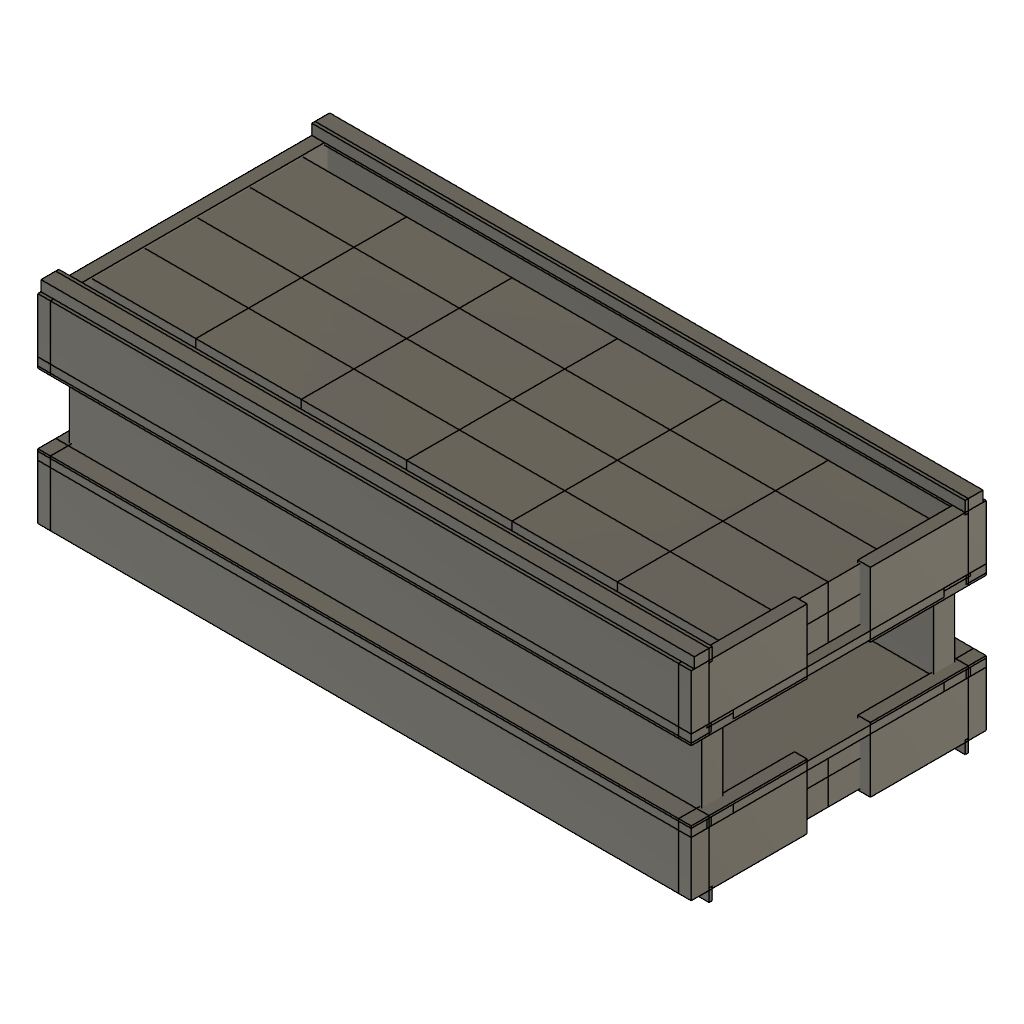
Magnetide-v23-full (Autodesk Fusion 360 design; units mm, degrees)
part number: 2026-10-21-11-29-40-472
Autodesk Fusion 360 part; units mm, degrees
ref_plane "WorkPlane1" through (0, 0, 7.75) normal (0, 0, 1) x (1, 0, 0)
sketch "low_floor_roof" plane through (0, 0, 7.75) normal (0, 0, 1) x (1, 0, 0)
  line L0 (-2, -20) -> (122, -20)
  line L1 (122, -20) -> (122, 20)
  line L2 (122, 20) -> (-2, 20)
  line L3 (-2, 20) -> (-2, -20)
extrude "Extrude1" add sketch "low_floor_roof" along normal mid plane 1.5 makes body 1
ref_plane "WorkPlane2" through (0, 0, 8.25) normal (0, 0, 1) x (1, 0, 0)
sketch "low_seat_R" plane through (0, 0, 8.25) normal (0, 0, 1) x (1, 0, 0)
  line L0 (-2, 20) -> (122, 20)
  line L1 (122, 20) -> (122, 25)
  line L2 (122, 25) -> (-2, 25)
  line L3 (-2, 25) -> (-2, 20)
extrude "Extrude2" add sketch "low_seat_R" along normal mid plane 0.5 separate body makes body 2
ref_plane "WorkPlane3" through (0, 0, 8.25) normal (0, 0, 1) x (1, 0, 0)
sketch "low_seat_L" plane through (0, 0, 8.25) normal (0, 0, 1) x (1, 0, 0)
  line L0 (-2, -25) -> (122, -25)
  line L1 (122, -25) -> (122, -20)
  line L2 (122, -20) -> (-2, -20)
  line L3 (-2, -20) -> (-2, -25)
extrude "Extrude3" add sketch "low_seat_L" along normal mid plane 0.5 separate body makes body 3
ref_plane "WorkPlane4" through (0, 0, 7.75) normal (0, 0, 1) x (1, 0, 0)
sketch "low_out_R" plane through (0, 0, 7.75) normal (0, 0, 1) x (1, 0, 0)
  line L0 (-2, 24.2) -> (122, 24.2)
  line L1 (122, 24.2) -> (122, 28)
  line L2 (122, 28) -> (-2, 28)
  line L3 (-2, 28) -> (-2, 24.2)
extrude "Extrude4" add sketch "low_out_R" along normal mid plane 1.5 separate body makes body 4
ref_plane "WorkPlane5" through (0, 0, 7.75) normal (0, 0, 1) x (1, 0, 0)
sketch "low_out_L" plane through (0, 0, 7.75) normal (0, 0, 1) x (1, 0, 0)
  line L0 (-2, -28) -> (122, -28)
  line L1 (122, -28) -> (122, -24.2)
  line L2 (122, -24.2) -> (-2, -24.2)
  line L3 (-2, -24.2) -> (-2, -28)
extrude "Extrude5" add sketch "low_out_L" along normal mid plane 1.5 separate body makes body 5
ref_plane "WorkPlane6" through (0, 26.3, 0) normal (0, 1, 0) x (0, 0, 1)
sketch "low_wall_R" plane through (0, 26.3, 0) normal (0, 1, 0) x (1, 0, 0)
  line L0 (-2, -18.9) -> (122, -18.9)
  line L1 (122, -18.9) -> (122, -6.6)
  line L2 (122, -6.6) -> (-2, -6.6)
  line L3 (-2, -6.6) -> (-2, -18.9)
extrude "Extrude6" add sketch "low_wall_R" along normal mid plane 3.4 separate body makes body 6
ref_plane "WorkPlane7" through (0, -26.3, 0) normal (0, 1, 0) x (0, 0, 1)
sketch "low_wall_L" plane through (0, -26.3, 0) normal (0, 1, 0) x (1, 0, 0)
  line L0 (-2, -18.9) -> (122, -18.9)
  line L1 (122, -18.9) -> (122, -6.6)
  line L2 (122, -6.6) -> (-2, -6.6)
  line L3 (-2, -6.6) -> (-2, -18.9)
extrude "Extrude7" add sketch "low_wall_L" along normal mid plane 3.4 separate body makes body 7
ref_plane "WorkPlane8" through (-0.8, 0, 0) normal (1, 0, 0) x (0, 1, 0)
sketch "low_end_front" plane through (-0.8, 0, 0) normal (1, 0, 0) x (0, 0, -1)
  line L0 (-18.9, -28) -> (-6.6, -28)
  line L1 (-6.6, -28) -> (-6.6, 28)
  line L2 (-6.6, 28) -> (-18.9, 28)
  line L3 (-18.9, 28) -> (-18.9, -28)
extrude "Extrude8" add sketch "low_end_front" along normal mid plane 2.4 separate body makes body 8
ref_plane "WorkPlane9" through (120.8, 0, 0) normal (1, 0, 0) x (0, 1, 0)
sketch "low_end_back_R" plane through (120.8, 0, 0) normal (1, 0, 0) x (0, 0, -1)
  line L0 (-18.9, 6) -> (-6.6, 6)
  line L1 (-6.6, 6) -> (-6.6, 28)
  line L2 (-6.6, 28) -> (-18.9, 28)
  line L3 (-18.9, 28) -> (-18.9, 6)
extrude "Extrude9" add sketch "low_end_back_R" along normal mid plane 2.4 separate body makes body 9
ref_plane "WorkPlane10" through (120.8, 0, 0) normal (1, 0, 0) x (0, 1, 0)
sketch "low_end_back_L" plane through (120.8, 0, 0) normal (1, 0, 0) x (0, 0, -1)
  line L0 (-18.9, -28) -> (-6.6, -28)
  line L1 (-6.6, -28) -> (-6.6, -6)
  line L2 (-6.6, -6) -> (-18.9, -6)
  line L3 (-18.9, -6) -> (-18.9, -28)
extrude "Extrude10" add sketch "low_end_back_L" along normal mid plane 2.4 separate body makes body 10
ref_plane "WorkPlane11" through (0, 24.3, 0) normal (0, 1, 0) x (0, 0, 1)
sketch "low_lip_R" plane through (0, 24.3, 0) normal (0, 1, 0) x (1, 0, 0)
  line L0 (-2, -20.9) -> (122, -20.9)
  line L1 (122, -20.9) -> (122, -18.5)
  line L2 (122, -18.5) -> (-2, -18.5)
  line L3 (-2, -18.5) -> (-2, -20.9)
extrude "Extrude11" add sketch "low_lip_R" along normal mid plane 0.6 separate body makes body 11
ref_plane "WorkPlane12" through (0, -24.3, 0) normal (0, 1, 0) x (0, 0, 1)
sketch "low_lip_L" plane through (0, -24.3, 0) normal (0, 1, 0) x (1, 0, 0)
  line L0 (-2, -20.9) -> (122, -20.9)
  line L1 (122, -20.9) -> (122, -18.5)
  line L2 (122, -18.5) -> (-2, -18.5)
  line L3 (-2, -18.5) -> (-2, -20.9)
extrude "Extrude12" add sketch "low_lip_L" along normal mid plane 0.6 separate body makes body 12
ref_plane "WorkPlane13" through (0, 0, -7.75) normal (0, 0, 1) x (1, 0, 0)
sketch "up_floor_roof" plane through (0, 0, -7.75) normal (0, 0, 1) x (1, 0, 0)
  line L0 (-2, -20) -> (122, -20)
  line L1 (122, -20) -> (122, 20)
  line L2 (122, 20) -> (-2, 20)
  line L3 (-2, 20) -> (-2, -20)
extrude "Extrude13" add sketch "up_floor_roof" along normal mid plane 1.5 separate body makes body 13
ref_plane "WorkPlane14" through (0, 0, -7.75) normal (0, 0, 1) x (1, 0, 0)
sketch "up_seat_R" plane through (0, 0, -7.75) normal (0, 0, 1) x (1, 0, 0)
  line L0 (-2, 20) -> (122, 20)
  line L1 (122, 20) -> (122, 25)
  line L2 (122, 25) -> (-2, 25)
  line L3 (-2, 25) -> (-2, 20)
extrude "Extrude14" add sketch "up_seat_R" along normal mid plane 1.5 separate body makes body 14
ref_plane "WorkPlane15" through (0, 0, -7.75) normal (0, 0, 1) x (1, 0, 0)
sketch "up_seat_L" plane through (0, 0, -7.75) normal (0, 0, 1) x (1, 0, 0)
  line L0 (-2, -25) -> (122, -25)
  line L1 (122, -25) -> (122, -20)
  line L2 (122, -20) -> (-2, -20)
  line L3 (-2, -20) -> (-2, -25)
extrude "Extrude15" add sketch "up_seat_L" along normal mid plane 1.5 separate body makes body 15
ref_plane "WorkPlane16" through (0, 0, -7.75) normal (0, 0, 1) x (1, 0, 0)
sketch "up_out_R" plane through (0, 0, -7.75) normal (0, 0, 1) x (1, 0, 0)
  line L0 (-2, 24.2) -> (122, 24.2)
  line L1 (122, 24.2) -> (122, 28)
  line L2 (122, 28) -> (-2, 28)
  line L3 (-2, 28) -> (-2, 24.2)
extrude "Extrude16" add sketch "up_out_R" along normal mid plane 1.5 separate body makes body 16
ref_plane "WorkPlane17" through (0, 0, -7.75) normal (0, 0, 1) x (1, 0, 0)
sketch "up_out_L" plane through (0, 0, -7.75) normal (0, 0, 1) x (1, 0, 0)
  line L0 (-2, -28) -> (122, -28)
  line L1 (122, -28) -> (122, -24.2)
  line L2 (122, -24.2) -> (-2, -24.2)
  line L3 (-2, -24.2) -> (-2, -28)
extrude "Extrude17" add sketch "up_out_L" along normal mid plane 1.5 separate body makes body 17
ref_plane "WorkPlane18" through (0, 26.3, 0) normal (0, 1, 0) x (0, 0, 1)
sketch "up_wall_R" plane through (0, 26.3, 0) normal (0, 1, 0) x (1, 0, 0)
  line L0 (-2, 6.6) -> (122, 6.6)
  line L1 (122, 6.6) -> (122, 18.9)
  line L2 (122, 18.9) -> (-2, 18.9)
  line L3 (-2, 18.9) -> (-2, 6.6)
extrude "Extrude18" add sketch "up_wall_R" along normal mid plane 3.4 separate body makes body 18
ref_plane "WorkPlane19" through (0, -26.3, 0) normal (0, 1, 0) x (0, 0, 1)
sketch "up_wall_L" plane through (0, -26.3, 0) normal (0, 1, 0) x (1, 0, 0)
  line L0 (-2, 6.6) -> (122, 6.6)
  line L1 (122, 6.6) -> (122, 18.9)
  line L2 (122, 18.9) -> (-2, 18.9)
  line L3 (-2, 18.9) -> (-2, 6.6)
extrude "Extrude19" add sketch "up_wall_L" along normal mid plane 3.4 separate body makes body 19
ref_plane "WorkPlane20" through (-0.8, 0, 0) normal (1, 0, 0) x (0, 1, 0)
sketch "up_end_front" plane through (-0.8, 0, 0) normal (1, 0, 0) x (0, 0, -1)
  line L0 (6.6, -28) -> (18.9, -28)
  line L1 (18.9, -28) -> (18.9, 28)
  line L2 (18.9, 28) -> (6.6, 28)
  line L3 (6.6, 28) -> (6.6, -28)
extrude "Extrude20" add sketch "up_end_front" along normal mid plane 2.4 separate body makes body 20
ref_plane "WorkPlane21" through (120.8, 0, 0) normal (1, 0, 0) x (0, 1, 0)
sketch "up_end_back_R" plane through (120.8, 0, 0) normal (1, 0, 0) x (0, 0, -1)
  line L0 (6.6, 6) -> (18.9, 6)
  line L1 (18.9, 6) -> (18.9, 28)
  line L2 (18.9, 28) -> (6.6, 28)
  line L3 (6.6, 28) -> (6.6, 6)
extrude "Extrude21" add sketch "up_end_back_R" along normal mid plane 2.4 separate body makes body 21
ref_plane "WorkPlane22" through (120.8, 0, 0) normal (1, 0, 0) x (0, 1, 0)
sketch "up_end_back_L" plane through (120.8, 0, 0) normal (1, 0, 0) x (0, 0, -1)
  line L0 (6.6, -28) -> (18.9, -28)
  line L1 (18.9, -28) -> (18.9, -6)
  line L2 (18.9, -6) -> (6.6, -6)
  line L3 (6.6, -6) -> (6.6, -28)
extrude "Extrude22" add sketch "up_end_back_L" along normal mid plane 2.4 separate body makes body 22
ref_plane "WorkPlane23" through (0, 24.3, 0) normal (0, 1, 0) x (0, 0, 1)
sketch "up_lip_R" plane through (0, 24.3, 0) normal (0, 1, 0) x (1, 0, 0)
  line L0 (-2, 18.5) -> (122, 18.5)
  line L1 (122, 18.5) -> (122, 20.9)
  line L2 (122, 20.9) -> (-2, 20.9)
  line L3 (-2, 20.9) -> (-2, 18.5)
extrude "Extrude23" add sketch "up_lip_R" along normal mid plane 0.6 separate body makes body 23
ref_plane "WorkPlane24" through (0, -24.3, 0) normal (0, 1, 0) x (0, 0, 1)
sketch "up_lip_L" plane through (0, -24.3, 0) normal (0, 1, 0) x (1, 0, 0)
  line L0 (-2, 18.5) -> (122, 18.5)
  line L1 (122, 18.5) -> (122, 20.9)
  line L2 (122, 20.9) -> (-2, 20.9)
  line L3 (-2, 20.9) -> (-2, 18.5)
extrude "Extrude24" add sketch "up_lip_L" along normal mid plane 0.6 separate body makes body 24
ref_plane "WorkPlane25" through (0, 22, 0) normal (0, 1, 0) x (0, 0, 1)
sketch "graphite_R" plane through (0, 22, 0) normal (0, 1, 0) x (1, 0, 0)
  line L0 (0, -8) -> (120, -8)
  line L1 (120, -8) -> (120, 8)
  line L2 (120, 8) -> (0, 8)
  line L3 (0, 8) -> (0, -8)
extrude "Extrude25" add sketch "graphite_R" along normal mid plane 4 separate body makes body 25
ref_plane "WorkPlane26" through (0, -22, 0) normal (0, 1, 0) x (0, 0, 1)
sketch "graphite_L" plane through (0, -22, 0) normal (0, 1, 0) x (1, 0, 0)
  line L0 (0, -8) -> (120, -8)
  line L1 (120, -8) -> (120, 8)
  line L2 (120, 8) -> (0, 8)
  line L3 (0, 8) -> (0, -8)
extrude "Extrude26" add sketch "graphite_L" along normal mid plane 4 separate body makes body 26
ref_plane "WorkPlane27" through (0, 25.7, 0) normal (0, 1, 0) x (0, 0, 1)
sketch "iron_R" plane through (0, 25.7, 0) normal (0, 1, 0) x (1, 0, 0)
  line L0 (-2, -20.9) -> (122, -20.9)
  line L1 (122, -20.9) -> (122, -18.9)
  line L2 (122, -18.9) -> (-2, -18.9)
  line L3 (-2, -18.9) -> (-2, -20.9)
extrude "Extrude27" add sketch "iron_R" along normal mid plane 3.4 separate body makes body 27
ref_plane "WorkPlane28" through (0, -25.7, 0) normal (0, 1, 0) x (0, 0, 1)
sketch "iron_L" plane through (0, -25.7, 0) normal (0, 1, 0) x (1, 0, 0)
  line L0 (-2, -20.9) -> (122, -20.9)
  line L1 (122, -20.9) -> (122, -18.9)
  line L2 (122, -18.9) -> (-2, -18.9)
  line L3 (-2, -18.9) -> (-2, -20.9)
extrude "Extrude28" add sketch "iron_L" along normal mid plane 3.4 separate body makes body 28
ref_plane "WorkPlane29" through (0, 0, 11) normal (0, 0, 1) x (1, 0, 0)
sketch "tile_N_0_0_0" plane through (0, 0, 11) normal (0, 0, 1) x (1, 0, 0)
  line L0 (0, -20) -> (20, -20)
  line L1 (20, -20) -> (20, -10)
  line L2 (20, -10) -> (0, -10)
  line L3 (0, -10) -> (0, -20)
extrude "Extrude29" add sketch "tile_N_0_0_0" along normal mid plane 5 separate body makes body 29
ref_plane "WorkPlane30" through (0, 0, -11) normal (0, 0, 1) x (1, 0, 0)
sketch "tile_S_0_0_0" plane through (0, 0, -11) normal (0, 0, 1) x (1, 0, 0)
  line L0 (0, -20) -> (20, -20)
  line L1 (20, -20) -> (20, -10)
  line L2 (20, -10) -> (0, -10)
  line L3 (0, -10) -> (0, -20)
extrude "Extrude30" add sketch "tile_S_0_0_0" along normal mid plane 5 separate body makes body 30
ref_plane "WorkPlane31" through (0, 0, 16) normal (0, 0, 1) x (1, 0, 0)
sketch "tile_N_0_0_1" plane through (0, 0, 16) normal (0, 0, 1) x (1, 0, 0)
  line L0 (0, -20) -> (20, -20)
  line L1 (20, -20) -> (20, -10)
  line L2 (20, -10) -> (0, -10)
  line L3 (0, -10) -> (0, -20)
extrude "Extrude31" add sketch "tile_N_0_0_1" along normal mid plane 5 separate body makes body 31
ref_plane "WorkPlane32" through (0, 0, -16) normal (0, 0, 1) x (1, 0, 0)
sketch "tile_S_0_0_1" plane through (0, 0, -16) normal (0, 0, 1) x (1, 0, 0)
  line L0 (0, -20) -> (20, -20)
  line L1 (20, -20) -> (20, -10)
  line L2 (20, -10) -> (0, -10)
  line L3 (0, -10) -> (0, -20)
extrude "Extrude32" add sketch "tile_S_0_0_1" along normal mid plane 5 separate body makes body 32
ref_plane "WorkPlane33" through (0, 0, 11) normal (0, 0, 1) x (1, 0, 0)
sketch "tile_N_0_1_0" plane through (0, 0, 11) normal (0, 0, 1) x (1, 0, 0)
  line L0 (0, -10) -> (20, -10)
  line L1 (20, -10) -> (20, 0)
  line L2 (20, 0) -> (0, 0)
  line L3 (0, 0) -> (0, -10)
extrude "Extrude33" add sketch "tile_N_0_1_0" along normal mid plane 5 separate body makes body 33
ref_plane "WorkPlane34" through (0, 0, -11) normal (0, 0, 1) x (1, 0, 0)
sketch "tile_S_0_1_0" plane through (0, 0, -11) normal (0, 0, 1) x (1, 0, 0)
  line L0 (0, -10) -> (20, -10)
  line L1 (20, -10) -> (20, 0)
  line L2 (20, 0) -> (0, 0)
  line L3 (0, 0) -> (0, -10)
extrude "Extrude34" add sketch "tile_S_0_1_0" along normal mid plane 5 separate body makes body 34
ref_plane "WorkPlane35" through (0, 0, 16) normal (0, 0, 1) x (1, 0, 0)
sketch "tile_N_0_1_1" plane through (0, 0, 16) normal (0, 0, 1) x (1, 0, 0)
  line L0 (0, -10) -> (20, -10)
  line L1 (20, -10) -> (20, 0)
  line L2 (20, 0) -> (0, 0)
  line L3 (0, 0) -> (0, -10)
extrude "Extrude35" add sketch "tile_N_0_1_1" along normal mid plane 5 separate body makes body 35
ref_plane "WorkPlane36" through (0, 0, -16) normal (0, 0, 1) x (1, 0, 0)
sketch "tile_S_0_1_1" plane through (0, 0, -16) normal (0, 0, 1) x (1, 0, 0)
  line L0 (0, -10) -> (20, -10)
  line L1 (20, -10) -> (20, 0)
  line L2 (20, 0) -> (0, 0)
  line L3 (0, 0) -> (0, -10)
extrude "Extrude36" add sketch "tile_S_0_1_1" along normal mid plane 5 separate body makes body 36
ref_plane "WorkPlane37" through (0, 0, 11) normal (0, 0, 1) x (1, 0, 0)
sketch "tile_N_0_2_0" plane through (0, 0, 11) normal (0, 0, 1) x (1, 0, 0)
  line L0 (0, 0) -> (20, 0)
  line L1 (20, 0) -> (20, 10)
  line L2 (20, 10) -> (0, 10)
  line L3 (0, 10) -> (0, 0)
extrude "Extrude37" add sketch "tile_N_0_2_0" along normal mid plane 5 separate body makes body 37
ref_plane "WorkPlane38" through (0, 0, -11) normal (0, 0, 1) x (1, 0, 0)
sketch "tile_S_0_2_0" plane through (0, 0, -11) normal (0, 0, 1) x (1, 0, 0)
  line L0 (0, 0) -> (20, 0)
  line L1 (20, 0) -> (20, 10)
  line L2 (20, 10) -> (0, 10)
  line L3 (0, 10) -> (0, 0)
extrude "Extrude38" add sketch "tile_S_0_2_0" along normal mid plane 5 separate body makes body 38
ref_plane "WorkPlane39" through (0, 0, 16) normal (0, 0, 1) x (1, 0, 0)
sketch "tile_N_0_2_1" plane through (0, 0, 16) normal (0, 0, 1) x (1, 0, 0)
  line L0 (0, 0) -> (20, 0)
  line L1 (20, 0) -> (20, 10)
  line L2 (20, 10) -> (0, 10)
  line L3 (0, 10) -> (0, 0)
extrude "Extrude39" add sketch "tile_N_0_2_1" along normal mid plane 5 separate body makes body 39
ref_plane "WorkPlane40" through (0, 0, -16) normal (0, 0, 1) x (1, 0, 0)
sketch "tile_S_0_2_1" plane through (0, 0, -16) normal (0, 0, 1) x (1, 0, 0)
  line L0 (0, 0) -> (20, 0)
  line L1 (20, 0) -> (20, 10)
  line L2 (20, 10) -> (0, 10)
  line L3 (0, 10) -> (0, 0)
extrude "Extrude40" add sketch "tile_S_0_2_1" along normal mid plane 5 separate body makes body 40
ref_plane "WorkPlane41" through (0, 0, 11) normal (0, 0, 1) x (1, 0, 0)
sketch "tile_N_0_3_0" plane through (0, 0, 11) normal (0, 0, 1) x (1, 0, 0)
  line L0 (0, 10) -> (20, 10)
  line L1 (20, 10) -> (20, 20)
  line L2 (20, 20) -> (0, 20)
  line L3 (0, 20) -> (0, 10)
extrude "Extrude41" add sketch "tile_N_0_3_0" along normal mid plane 5 separate body makes body 41
ref_plane "WorkPlane42" through (0, 0, -11) normal (0, 0, 1) x (1, 0, 0)
sketch "tile_S_0_3_0" plane through (0, 0, -11) normal (0, 0, 1) x (1, 0, 0)
  line L0 (0, 10) -> (20, 10)
  line L1 (20, 10) -> (20, 20)
  line L2 (20, 20) -> (0, 20)
  line L3 (0, 20) -> (0, 10)
extrude "Extrude42" add sketch "tile_S_0_3_0" along normal mid plane 5 separate body makes body 42
ref_plane "WorkPlane43" through (0, 0, 16) normal (0, 0, 1) x (1, 0, 0)
sketch "tile_N_0_3_1" plane through (0, 0, 16) normal (0, 0, 1) x (1, 0, 0)
  line L0 (0, 10) -> (20, 10)
  line L1 (20, 10) -> (20, 20)
  line L2 (20, 20) -> (0, 20)
  line L3 (0, 20) -> (0, 10)
extrude "Extrude43" add sketch "tile_N_0_3_1" along normal mid plane 5 separate body makes body 43
ref_plane "WorkPlane44" through (0, 0, -16) normal (0, 0, 1) x (1, 0, 0)
sketch "tile_S_0_3_1" plane through (0, 0, -16) normal (0, 0, 1) x (1, 0, 0)
  line L0 (0, 10) -> (20, 10)
  line L1 (20, 10) -> (20, 20)
  line L2 (20, 20) -> (0, 20)
  line L3 (0, 20) -> (0, 10)
extrude "Extrude44" add sketch "tile_S_0_3_1" along normal mid plane 5 separate body makes body 44
ref_plane "WorkPlane45" through (0, 0, 11) normal (0, 0, 1) x (1, 0, 0)
sketch "tile_N_1_0_0" plane through (0, 0, 11) normal (0, 0, 1) x (1, 0, 0)
  line L0 (20, -20) -> (40, -20)
  line L1 (40, -20) -> (40, -10)
  line L2 (40, -10) -> (20, -10)
  line L3 (20, -10) -> (20, -20)
extrude "Extrude45" add sketch "tile_N_1_0_0" along normal mid plane 5 separate body makes body 45
ref_plane "WorkPlane46" through (0, 0, -11) normal (0, 0, 1) x (1, 0, 0)
sketch "tile_S_1_0_0" plane through (0, 0, -11) normal (0, 0, 1) x (1, 0, 0)
  line L0 (20, -20) -> (40, -20)
  line L1 (40, -20) -> (40, -10)
  line L2 (40, -10) -> (20, -10)
  line L3 (20, -10) -> (20, -20)
extrude "Extrude46" add sketch "tile_S_1_0_0" along normal mid plane 5 separate body makes body 46
ref_plane "WorkPlane47" through (0, 0, 16) normal (0, 0, 1) x (1, 0, 0)
sketch "tile_N_1_0_1" plane through (0, 0, 16) normal (0, 0, 1) x (1, 0, 0)
  line L0 (20, -20) -> (40, -20)
  line L1 (40, -20) -> (40, -10)
  line L2 (40, -10) -> (20, -10)
  line L3 (20, -10) -> (20, -20)
extrude "Extrude47" add sketch "tile_N_1_0_1" along normal mid plane 5 separate body makes body 47
ref_plane "WorkPlane48" through (0, 0, -16) normal (0, 0, 1) x (1, 0, 0)
sketch "tile_S_1_0_1" plane through (0, 0, -16) normal (0, 0, 1) x (1, 0, 0)
  line L0 (20, -20) -> (40, -20)
  line L1 (40, -20) -> (40, -10)
  line L2 (40, -10) -> (20, -10)
  line L3 (20, -10) -> (20, -20)
extrude "Extrude48" add sketch "tile_S_1_0_1" along normal mid plane 5 separate body makes body 48
ref_plane "WorkPlane49" through (0, 0, 11) normal (0, 0, 1) x (1, 0, 0)
sketch "tile_N_1_1_0" plane through (0, 0, 11) normal (0, 0, 1) x (1, 0, 0)
  line L0 (20, -10) -> (40, -10)
  line L1 (40, -10) -> (40, 0)
  line L2 (40, 0) -> (20, 0)
  line L3 (20, 0) -> (20, -10)
extrude "Extrude49" add sketch "tile_N_1_1_0" along normal mid plane 5 separate body makes body 49
ref_plane "WorkPlane50" through (0, 0, -11) normal (0, 0, 1) x (1, 0, 0)
sketch "tile_S_1_1_0" plane through (0, 0, -11) normal (0, 0, 1) x (1, 0, 0)
  line L0 (20, -10) -> (40, -10)
  line L1 (40, -10) -> (40, 0)
  line L2 (40, 0) -> (20, 0)
  line L3 (20, 0) -> (20, -10)
extrude "Extrude50" add sketch "tile_S_1_1_0" along normal mid plane 5 separate body makes body 50
ref_plane "WorkPlane51" through (0, 0, 16) normal (0, 0, 1) x (1, 0, 0)
sketch "tile_N_1_1_1" plane through (0, 0, 16) normal (0, 0, 1) x (1, 0, 0)
  line L0 (20, -10) -> (40, -10)
  line L1 (40, -10) -> (40, 0)
  line L2 (40, 0) -> (20, 0)
  line L3 (20, 0) -> (20, -10)
extrude "Extrude51" add sketch "tile_N_1_1_1" along normal mid plane 5 separate body makes body 51
ref_plane "WorkPlane52" through (0, 0, -16) normal (0, 0, 1) x (1, 0, 0)
sketch "tile_S_1_1_1" plane through (0, 0, -16) normal (0, 0, 1) x (1, 0, 0)
  line L0 (20, -10) -> (40, -10)
  line L1 (40, -10) -> (40, 0)
  line L2 (40, 0) -> (20, 0)
  line L3 (20, 0) -> (20, -10)
extrude "Extrude52" add sketch "tile_S_1_1_1" along normal mid plane 5 separate body makes body 52
ref_plane "WorkPlane53" through (0, 0, 11) normal (0, 0, 1) x (1, 0, 0)
sketch "tile_N_1_2_0" plane through (0, 0, 11) normal (0, 0, 1) x (1, 0, 0)
  line L0 (20, 0) -> (40, 0)
  line L1 (40, 0) -> (40, 10)
  line L2 (40, 10) -> (20, 10)
  line L3 (20, 10) -> (20, 0)
extrude "Extrude53" add sketch "tile_N_1_2_0" along normal mid plane 5 separate body makes body 53
ref_plane "WorkPlane54" through (0, 0, -11) normal (0, 0, 1) x (1, 0, 0)
sketch "tile_S_1_2_0" plane through (0, 0, -11) normal (0, 0, 1) x (1, 0, 0)
  line L0 (20, 0) -> (40, 0)
  line L1 (40, 0) -> (40, 10)
  line L2 (40, 10) -> (20, 10)
  line L3 (20, 10) -> (20, 0)
extrude "Extrude54" add sketch "tile_S_1_2_0" along normal mid plane 5 separate body makes body 54
ref_plane "WorkPlane55" through (0, 0, 16) normal (0, 0, 1) x (1, 0, 0)
sketch "tile_N_1_2_1" plane through (0, 0, 16) normal (0, 0, 1) x (1, 0, 0)
  line L0 (20, 0) -> (40, 0)
  line L1 (40, 0) -> (40, 10)
  line L2 (40, 10) -> (20, 10)
  line L3 (20, 10) -> (20, 0)
extrude "Extrude55" add sketch "tile_N_1_2_1" along normal mid plane 5 separate body makes body 55
ref_plane "WorkPlane56" through (0, 0, -16) normal (0, 0, 1) x (1, 0, 0)
sketch "tile_S_1_2_1" plane through (0, 0, -16) normal (0, 0, 1) x (1, 0, 0)
  line L0 (20, 0) -> (40, 0)
  line L1 (40, 0) -> (40, 10)
  line L2 (40, 10) -> (20, 10)
  line L3 (20, 10) -> (20, 0)
extrude "Extrude56" add sketch "tile_S_1_2_1" along normal mid plane 5 separate body makes body 56
ref_plane "WorkPlane57" through (0, 0, 11) normal (0, 0, 1) x (1, 0, 0)
sketch "tile_N_1_3_0" plane through (0, 0, 11) normal (0, 0, 1) x (1, 0, 0)
  line L0 (20, 10) -> (40, 10)
  line L1 (40, 10) -> (40, 20)
  line L2 (40, 20) -> (20, 20)
  line L3 (20, 20) -> (20, 10)
extrude "Extrude57" add sketch "tile_N_1_3_0" along normal mid plane 5 separate body makes body 57
ref_plane "WorkPlane58" through (0, 0, -11) normal (0, 0, 1) x (1, 0, 0)
sketch "tile_S_1_3_0" plane through (0, 0, -11) normal (0, 0, 1) x (1, 0, 0)
  line L0 (20, 10) -> (40, 10)
  line L1 (40, 10) -> (40, 20)
  line L2 (40, 20) -> (20, 20)
  line L3 (20, 20) -> (20, 10)
extrude "Extrude58" add sketch "tile_S_1_3_0" along normal mid plane 5 separate body makes body 58
ref_plane "WorkPlane59" through (0, 0, 16) normal (0, 0, 1) x (1, 0, 0)
sketch "tile_N_1_3_1" plane through (0, 0, 16) normal (0, 0, 1) x (1, 0, 0)
  line L0 (20, 10) -> (40, 10)
  line L1 (40, 10) -> (40, 20)
  line L2 (40, 20) -> (20, 20)
  line L3 (20, 20) -> (20, 10)
extrude "Extrude59" add sketch "tile_N_1_3_1" along normal mid plane 5 separate body makes body 59
ref_plane "WorkPlane60" through (0, 0, -16) normal (0, 0, 1) x (1, 0, 0)
sketch "tile_S_1_3_1" plane through (0, 0, -16) normal (0, 0, 1) x (1, 0, 0)
  line L0 (20, 10) -> (40, 10)
  line L1 (40, 10) -> (40, 20)
  line L2 (40, 20) -> (20, 20)
  line L3 (20, 20) -> (20, 10)
extrude "Extrude60" add sketch "tile_S_1_3_1" along normal mid plane 5 separate body makes body 60
ref_plane "WorkPlane61" through (0, 0, 11) normal (0, 0, 1) x (1, 0, 0)
sketch "tile_N_2_0_0" plane through (0, 0, 11) normal (0, 0, 1) x (1, 0, 0)
  line L0 (40, -20) -> (60, -20)
  line L1 (60, -20) -> (60, -10)
  line L2 (60, -10) -> (40, -10)
  line L3 (40, -10) -> (40, -20)
extrude "Extrude61" add sketch "tile_N_2_0_0" along normal mid plane 5 separate body makes body 61
ref_plane "WorkPlane62" through (0, 0, -11) normal (0, 0, 1) x (1, 0, 0)
sketch "tile_S_2_0_0" plane through (0, 0, -11) normal (0, 0, 1) x (1, 0, 0)
  line L0 (40, -20) -> (60, -20)
  line L1 (60, -20) -> (60, -10)
  line L2 (60, -10) -> (40, -10)
  line L3 (40, -10) -> (40, -20)
extrude "Extrude62" add sketch "tile_S_2_0_0" along normal mid plane 5 separate body makes body 62
ref_plane "WorkPlane63" through (0, 0, 16) normal (0, 0, 1) x (1, 0, 0)
sketch "tile_N_2_0_1" plane through (0, 0, 16) normal (0, 0, 1) x (1, 0, 0)
  line L0 (40, -20) -> (60, -20)
  line L1 (60, -20) -> (60, -10)
  line L2 (60, -10) -> (40, -10)
  line L3 (40, -10) -> (40, -20)
extrude "Extrude63" add sketch "tile_N_2_0_1" along normal mid plane 5 separate body makes body 63
ref_plane "WorkPlane64" through (0, 0, -16) normal (0, 0, 1) x (1, 0, 0)
sketch "tile_S_2_0_1" plane through (0, 0, -16) normal (0, 0, 1) x (1, 0, 0)
  line L0 (40, -20) -> (60, -20)
  line L1 (60, -20) -> (60, -10)
  line L2 (60, -10) -> (40, -10)
  line L3 (40, -10) -> (40, -20)
extrude "Extrude64" add sketch "tile_S_2_0_1" along normal mid plane 5 separate body makes body 64
ref_plane "WorkPlane65" through (0, 0, 11) normal (0, 0, 1) x (1, 0, 0)
sketch "tile_N_2_1_0" plane through (0, 0, 11) normal (0, 0, 1) x (1, 0, 0)
  line L0 (40, -10) -> (60, -10)
  line L1 (60, -10) -> (60, 0)
  line L2 (60, 0) -> (40, 0)
  line L3 (40, 0) -> (40, -10)
extrude "Extrude65" add sketch "tile_N_2_1_0" along normal mid plane 5 separate body makes body 65
ref_plane "WorkPlane66" through (0, 0, -11) normal (0, 0, 1) x (1, 0, 0)
sketch "tile_S_2_1_0" plane through (0, 0, -11) normal (0, 0, 1) x (1, 0, 0)
  line L0 (40, -10) -> (60, -10)
  line L1 (60, -10) -> (60, 0)
  line L2 (60, 0) -> (40, 0)
  line L3 (40, 0) -> (40, -10)
extrude "Extrude66" add sketch "tile_S_2_1_0" along normal mid plane 5 separate body makes body 66
ref_plane "WorkPlane67" through (0, 0, 16) normal (0, 0, 1) x (1, 0, 0)
sketch "tile_N_2_1_1" plane through (0, 0, 16) normal (0, 0, 1) x (1, 0, 0)
  line L0 (40, -10) -> (60, -10)
  line L1 (60, -10) -> (60, 0)
  line L2 (60, 0) -> (40, 0)
  line L3 (40, 0) -> (40, -10)
extrude "Extrude67" add sketch "tile_N_2_1_1" along normal mid plane 5 separate body makes body 67
ref_plane "WorkPlane68" through (0, 0, -16) normal (0, 0, 1) x (1, 0, 0)
sketch "tile_S_2_1_1" plane through (0, 0, -16) normal (0, 0, 1) x (1, 0, 0)
  line L0 (40, -10) -> (60, -10)
  line L1 (60, -10) -> (60, 0)
  line L2 (60, 0) -> (40, 0)
  line L3 (40, 0) -> (40, -10)
extrude "Extrude68" add sketch "tile_S_2_1_1" along normal mid plane 5 separate body makes body 68
ref_plane "WorkPlane69" through (0, 0, 11) normal (0, 0, 1) x (1, 0, 0)
sketch "tile_N_2_2_0" plane through (0, 0, 11) normal (0, 0, 1) x (1, 0, 0)
  line L0 (40, 0) -> (60, 0)
  line L1 (60, 0) -> (60, 10)
  line L2 (60, 10) -> (40, 10)
  line L3 (40, 10) -> (40, 0)
extrude "Extrude69" add sketch "tile_N_2_2_0" along normal mid plane 5 separate body makes body 69
ref_plane "WorkPlane70" through (0, 0, -11) normal (0, 0, 1) x (1, 0, 0)
sketch "tile_S_2_2_0" plane through (0, 0, -11) normal (0, 0, 1) x (1, 0, 0)
  line L0 (40, 0) -> (60, 0)
  line L1 (60, 0) -> (60, 10)
  line L2 (60, 10) -> (40, 10)
  line L3 (40, 10) -> (40, 0)
extrude "Extrude70" add sketch "tile_S_2_2_0" along normal mid plane 5 separate body makes body 70
ref_plane "WorkPlane71" through (0, 0, 16) normal (0, 0, 1) x (1, 0, 0)
sketch "tile_N_2_2_1" plane through (0, 0, 16) normal (0, 0, 1) x (1, 0, 0)
  line L0 (40, 0) -> (60, 0)
  line L1 (60, 0) -> (60, 10)
  line L2 (60, 10) -> (40, 10)
  line L3 (40, 10) -> (40, 0)
extrude "Extrude71" add sketch "tile_N_2_2_1" along normal mid plane 5 separate body makes body 71
ref_plane "WorkPlane72" through (0, 0, -16) normal (0, 0, 1) x (1, 0, 0)
sketch "tile_S_2_2_1" plane through (0, 0, -16) normal (0, 0, 1) x (1, 0, 0)
  line L0 (40, 0) -> (60, 0)
  line L1 (60, 0) -> (60, 10)
  line L2 (60, 10) -> (40, 10)
  line L3 (40, 10) -> (40, 0)
extrude "Extrude72" add sketch "tile_S_2_2_1" along normal mid plane 5 separate body makes body 72
ref_plane "WorkPlane73" through (0, 0, 11) normal (0, 0, 1) x (1, 0, 0)
sketch "tile_N_2_3_0" plane through (0, 0, 11) normal (0, 0, 1) x (1, 0, 0)
  line L0 (40, 10) -> (60, 10)
  line L1 (60, 10) -> (60, 20)
  line L2 (60, 20) -> (40, 20)
  line L3 (40, 20) -> (40, 10)
extrude "Extrude73" add sketch "tile_N_2_3_0" along normal mid plane 5 separate body makes body 73
ref_plane "WorkPlane74" through (0, 0, -11) normal (0, 0, 1) x (1, 0, 0)
sketch "tile_S_2_3_0" plane through (0, 0, -11) normal (0, 0, 1) x (1, 0, 0)
  line L0 (40, 10) -> (60, 10)
  line L1 (60, 10) -> (60, 20)
  line L2 (60, 20) -> (40, 20)
  line L3 (40, 20) -> (40, 10)
extrude "Extrude74" add sketch "tile_S_2_3_0" along normal mid plane 5 separate body makes body 74
ref_plane "WorkPlane75" through (0, 0, 16) normal (0, 0, 1) x (1, 0, 0)
sketch "tile_N_2_3_1" plane through (0, 0, 16) normal (0, 0, 1) x (1, 0, 0)
  line L0 (40, 10) -> (60, 10)
  line L1 (60, 10) -> (60, 20)
  line L2 (60, 20) -> (40, 20)
  line L3 (40, 20) -> (40, 10)
extrude "Extrude75" add sketch "tile_N_2_3_1" along normal mid plane 5 separate body makes body 75
ref_plane "WorkPlane76" through (0, 0, -16) normal (0, 0, 1) x (1, 0, 0)
sketch "tile_S_2_3_1" plane through (0, 0, -16) normal (0, 0, 1) x (1, 0, 0)
  line L0 (40, 10) -> (60, 10)
  line L1 (60, 10) -> (60, 20)
  line L2 (60, 20) -> (40, 20)
  line L3 (40, 20) -> (40, 10)
extrude "Extrude76" add sketch "tile_S_2_3_1" along normal mid plane 5 separate body makes body 76
ref_plane "WorkPlane77" through (0, 0, 11) normal (0, 0, 1) x (1, 0, 0)
sketch "tile_N_3_0_0" plane through (0, 0, 11) normal (0, 0, 1) x (1, 0, 0)
  line L0 (60, -20) -> (80, -20)
  line L1 (80, -20) -> (80, -10)
  line L2 (80, -10) -> (60, -10)
  line L3 (60, -10) -> (60, -20)
extrude "Extrude77" add sketch "tile_N_3_0_0" along normal mid plane 5 separate body makes body 77
ref_plane "WorkPlane78" through (0, 0, -11) normal (0, 0, 1) x (1, 0, 0)
sketch "tile_S_3_0_0" plane through (0, 0, -11) normal (0, 0, 1) x (1, 0, 0)
  line L0 (60, -20) -> (80, -20)
  line L1 (80, -20) -> (80, -10)
  line L2 (80, -10) -> (60, -10)
  line L3 (60, -10) -> (60, -20)
extrude "Extrude78" add sketch "tile_S_3_0_0" along normal mid plane 5 separate body makes body 78
ref_plane "WorkPlane79" through (0, 0, 16) normal (0, 0, 1) x (1, 0, 0)
sketch "tile_N_3_0_1" plane through (0, 0, 16) normal (0, 0, 1) x (1, 0, 0)
  line L0 (60, -20) -> (80, -20)
  line L1 (80, -20) -> (80, -10)
  line L2 (80, -10) -> (60, -10)
  line L3 (60, -10) -> (60, -20)
extrude "Extrude79" add sketch "tile_N_3_0_1" along normal mid plane 5 separate body makes body 79
ref_plane "WorkPlane80" through (0, 0, -16) normal (0, 0, 1) x (1, 0, 0)
sketch "tile_S_3_0_1" plane through (0, 0, -16) normal (0, 0, 1) x (1, 0, 0)
  line L0 (60, -20) -> (80, -20)
  line L1 (80, -20) -> (80, -10)
  line L2 (80, -10) -> (60, -10)
  line L3 (60, -10) -> (60, -20)
extrude "Extrude80" add sketch "tile_S_3_0_1" along normal mid plane 5 separate body makes body 80
ref_plane "WorkPlane81" through (0, 0, 11) normal (0, 0, 1) x (1, 0, 0)
sketch "tile_N_3_1_0" plane through (0, 0, 11) normal (0, 0, 1) x (1, 0, 0)
  line L0 (60, -10) -> (80, -10)
  line L1 (80, -10) -> (80, 0)
  line L2 (80, 0) -> (60, 0)
  line L3 (60, 0) -> (60, -10)
extrude "Extrude81" add sketch "tile_N_3_1_0" along normal mid plane 5 separate body makes body 81
ref_plane "WorkPlane82" through (0, 0, -11) normal (0, 0, 1) x (1, 0, 0)
sketch "tile_S_3_1_0" plane through (0, 0, -11) normal (0, 0, 1) x (1, 0, 0)
  line L0 (60, -10) -> (80, -10)
  line L1 (80, -10) -> (80, 0)
  line L2 (80, 0) -> (60, 0)
  line L3 (60, 0) -> (60, -10)
extrude "Extrude82" add sketch "tile_S_3_1_0" along normal mid plane 5 separate body makes body 82
ref_plane "WorkPlane83" through (0, 0, 16) normal (0, 0, 1) x (1, 0, 0)
sketch "tile_N_3_1_1" plane through (0, 0, 16) normal (0, 0, 1) x (1, 0, 0)
  line L0 (60, -10) -> (80, -10)
  line L1 (80, -10) -> (80, 0)
  line L2 (80, 0) -> (60, 0)
  line L3 (60, 0) -> (60, -10)
extrude "Extrude83" add sketch "tile_N_3_1_1" along normal mid plane 5 separate body makes body 83
ref_plane "WorkPlane84" through (0, 0, -16) normal (0, 0, 1) x (1, 0, 0)
sketch "tile_S_3_1_1" plane through (0, 0, -16) normal (0, 0, 1) x (1, 0, 0)
  line L0 (60, -10) -> (80, -10)
  line L1 (80, -10) -> (80, 0)
  line L2 (80, 0) -> (60, 0)
  line L3 (60, 0) -> (60, -10)
extrude "Extrude84" add sketch "tile_S_3_1_1" along normal mid plane 5 separate body makes body 84
ref_plane "WorkPlane85" through (0, 0, 11) normal (0, 0, 1) x (1, 0, 0)
sketch "tile_N_3_2_0" plane through (0, 0, 11) normal (0, 0, 1) x (1, 0, 0)
  line L0 (60, 0) -> (80, 0)
  line L1 (80, 0) -> (80, 10)
  line L2 (80, 10) -> (60, 10)
  line L3 (60, 10) -> (60, 0)
extrude "Extrude85" add sketch "tile_N_3_2_0" along normal mid plane 5 separate body makes body 85
ref_plane "WorkPlane86" through (0, 0, -11) normal (0, 0, 1) x (1, 0, 0)
sketch "tile_S_3_2_0" plane through (0, 0, -11) normal (0, 0, 1) x (1, 0, 0)
  line L0 (60, 0) -> (80, 0)
  line L1 (80, 0) -> (80, 10)
  line L2 (80, 10) -> (60, 10)
  line L3 (60, 10) -> (60, 0)
extrude "Extrude86" add sketch "tile_S_3_2_0" along normal mid plane 5 separate body makes body 86
ref_plane "WorkPlane87" through (0, 0, 16) normal (0, 0, 1) x (1, 0, 0)
sketch "tile_N_3_2_1" plane through (0, 0, 16) normal (0, 0, 1) x (1, 0, 0)
  line L0 (60, 0) -> (80, 0)
  line L1 (80, 0) -> (80, 10)
  line L2 (80, 10) -> (60, 10)
  line L3 (60, 10) -> (60, 0)
extrude "Extrude87" add sketch "tile_N_3_2_1" along normal mid plane 5 separate body makes body 87
ref_plane "WorkPlane88" through (0, 0, -16) normal (0, 0, 1) x (1, 0, 0)
sketch "tile_S_3_2_1" plane through (0, 0, -16) normal (0, 0, 1) x (1, 0, 0)
  line L0 (60, 0) -> (80, 0)
  line L1 (80, 0) -> (80, 10)
  line L2 (80, 10) -> (60, 10)
  line L3 (60, 10) -> (60, 0)
extrude "Extrude88" add sketch "tile_S_3_2_1" along normal mid plane 5 separate body makes body 88
ref_plane "WorkPlane89" through (0, 0, 11) normal (0, 0, 1) x (1, 0, 0)
sketch "tile_N_3_3_0" plane through (0, 0, 11) normal (0, 0, 1) x (1, 0, 0)
  line L0 (60, 10) -> (80, 10)
  line L1 (80, 10) -> (80, 20)
  line L2 (80, 20) -> (60, 20)
  line L3 (60, 20) -> (60, 10)
extrude "Extrude89" add sketch "tile_N_3_3_0" along normal mid plane 5 separate body makes body 89
ref_plane "WorkPlane90" through (0, 0, -11) normal (0, 0, 1) x (1, 0, 0)
sketch "tile_S_3_3_0" plane through (0, 0, -11) normal (0, 0, 1) x (1, 0, 0)
  line L0 (60, 10) -> (80, 10)
  line L1 (80, 10) -> (80, 20)
  line L2 (80, 20) -> (60, 20)
  line L3 (60, 20) -> (60, 10)
extrude "Extrude90" add sketch "tile_S_3_3_0" along normal mid plane 5 separate body makes body 90
ref_plane "WorkPlane91" through (0, 0, 16) normal (0, 0, 1) x (1, 0, 0)
sketch "tile_N_3_3_1" plane through (0, 0, 16) normal (0, 0, 1) x (1, 0, 0)
  line L0 (60, 10) -> (80, 10)
  line L1 (80, 10) -> (80, 20)
  line L2 (80, 20) -> (60, 20)
  line L3 (60, 20) -> (60, 10)
extrude "Extrude91" add sketch "tile_N_3_3_1" along normal mid plane 5 separate body makes body 91
ref_plane "WorkPlane92" through (0, 0, -16) normal (0, 0, 1) x (1, 0, 0)
sketch "tile_S_3_3_1" plane through (0, 0, -16) normal (0, 0, 1) x (1, 0, 0)
  line L0 (60, 10) -> (80, 10)
  line L1 (80, 10) -> (80, 20)
  line L2 (80, 20) -> (60, 20)
  line L3 (60, 20) -> (60, 10)
extrude "Extrude92" add sketch "tile_S_3_3_1" along normal mid plane 5 separate body makes body 92
ref_plane "WorkPlane93" through (0, 0, 11) normal (0, 0, 1) x (1, 0, 0)
sketch "tile_N_4_0_0" plane through (0, 0, 11) normal (0, 0, 1) x (1, 0, 0)
  line L0 (80, -20) -> (100, -20)
  line L1 (100, -20) -> (100, -10)
  line L2 (100, -10) -> (80, -10)
  line L3 (80, -10) -> (80, -20)
extrude "Extrude93" add sketch "tile_N_4_0_0" along normal mid plane 5 separate body makes body 93
ref_plane "WorkPlane94" through (0, 0, 0) normal (0, 1, 0) x (0, 0, 1)
sketch "tile_S_4_0_0" plane through (0, 0, -11) normal (0, 0, 1) x (1, 0, 0)
  line L0 (80, -20) -> (100, -20)
  line L1 (100, -20) -> (100, -10)
  line L2 (100, -10) -> (80, -10)
  line L3 (80, -10) -> (80, -20)
extrude "Extrude94" add sketch "tile_S_4_0_0" along normal mid plane 5 separate body makes body 94
ref_plane "WorkPlane95" through (0, 0, 16) normal (0, 0, 1) x (1, 0, 0)
sketch "tile_N_4_0_1" plane through (0, 0, 16) normal (0, 0, 1) x (1, 0, 0)
  line L0 (80, -20) -> (100, -20)
  line L1 (100, -20) -> (100, -10)
  line L2 (100, -10) -> (80, -10)
  line L3 (80, -10) -> (80, -20)
extrude "Extrude95" add sketch "tile_N_4_0_1" along normal mid plane 5 separate body makes body 95
ref_plane "WorkPlane96" through (0, 0, -16) normal (0, 0, 1) x (1, 0, 0)
sketch "tile_S_4_0_1" plane through (0, 0, -16) normal (0, 0, 1) x (1, 0, 0)
  line L0 (80, -20) -> (100, -20)
  line L1 (100, -20) -> (100, -10)
  line L2 (100, -10) -> (80, -10)
  line L3 (80, -10) -> (80, -20)
extrude "Extrude96" add sketch "tile_S_4_0_1" along normal mid plane 5 separate body makes body 96
ref_plane "WorkPlane97" through (0, 0, 11) normal (0, 0, 1) x (1, 0, 0)
sketch "tile_N_4_1_0" plane through (0, 0, 11) normal (0, 0, 1) x (1, 0, 0)
  line L0 (80, -10) -> (100, -10)
  line L1 (100, -10) -> (100, 0)
  line L2 (100, 0) -> (80, 0)
  line L3 (80, 0) -> (80, -10)
extrude "Extrude97" add sketch "tile_N_4_1_0" along normal mid plane 5 separate body makes body 97
ref_plane "WorkPlane98" through (0, 0, -11) normal (0, 0, 1) x (1, 0, 0)
sketch "tile_S_4_1_0" plane through (0, 0, -11) normal (0, 0, 1) x (1, 0, 0)
  line L0 (80, -10) -> (100, -10)
  line L1 (100, -10) -> (100, 0)
  line L2 (100, 0) -> (80, 0)
  line L3 (80, 0) -> (80, -10)
extrude "Extrude98" add sketch "tile_S_4_1_0" along normal mid plane 5 separate body makes body 98
ref_plane "WorkPlane99" through (0, 0, 16) normal (0, 0, 1) x (1, 0, 0)
sketch "tile_N_4_1_1" plane through (0, 0, 16) normal (0, 0, 1) x (1, 0, 0)
  line L0 (80, -10) -> (100, -10)
  line L1 (100, -10) -> (100, 0)
  line L2 (100, 0) -> (80, 0)
  line L3 (80, 0) -> (80, -10)
extrude "Extrude99" add sketch "tile_N_4_1_1" along normal mid plane 5 separate body makes body 99
ref_plane "WorkPlane100" through (0, 0, -16) normal (0, 0, 1) x (1, 0, 0)
sketch "tile_S_4_1_1" plane through (0, 0, -16) normal (0, 0, 1) x (1, 0, 0)
  line L0 (80, -10) -> (100, -10)
  line L1 (100, -10) -> (100, 0)
  line L2 (100, 0) -> (80, 0)
  line L3 (80, 0) -> (80, -10)
extrude "Extrude100" add sketch "tile_S_4_1_1" along normal mid plane 5 separate body makes body 100
ref_plane "WorkPlane101" through (0, 0, 11) normal (0, 0, 1) x (1, 0, 0)
sketch "tile_N_4_2_0" plane through (0, 0, 11) normal (0, 0, 1) x (1, 0, 0)
  line L0 (80, 0) -> (100, 0)
  line L1 (100, 0) -> (100, 10)
  line L2 (100, 10) -> (80, 10)
  line L3 (80, 10) -> (80, 0)
extrude "Extrude101" add sketch "tile_N_4_2_0" along normal mid plane 5 separate body makes body 101
ref_plane "WorkPlane102" through (0, 0, -11) normal (0, 0, 1) x (1, 0, 0)
sketch "tile_S_4_2_0" plane through (0, 0, -11) normal (0, 0, 1) x (1, 0, 0)
  line L0 (80, 0) -> (100, 0)
  line L1 (100, 0) -> (100, 10)
  line L2 (100, 10) -> (80, 10)
  line L3 (80, 10) -> (80, 0)
extrude "Extrude102" add sketch "tile_S_4_2_0" along normal mid plane 5 separate body makes body 102
ref_plane "WorkPlane103" through (0, 0, 16) normal (0, 0, 1) x (1, 0, 0)
sketch "tile_N_4_2_1" plane through (0, 0, 16) normal (0, 0, 1) x (1, 0, 0)
  line L0 (80, 0) -> (100, 0)
  line L1 (100, 0) -> (100, 10)
  line L2 (100, 10) -> (80, 10)
  line L3 (80, 10) -> (80, 0)
extrude "Extrude103" add sketch "tile_N_4_2_1" along normal mid plane 5 separate body makes body 103
ref_plane "WorkPlane104" through (0, 0, -16) normal (0, 0, 1) x (1, 0, 0)
sketch "tile_S_4_2_1" plane through (0, 0, -16) normal (0, 0, 1) x (1, 0, 0)
  line L0 (80, 0) -> (100, 0)
  line L1 (100, 0) -> (100, 10)
  line L2 (100, 10) -> (80, 10)
  line L3 (80, 10) -> (80, 0)
extrude "Extrude104" add sketch "tile_S_4_2_1" along normal mid plane 5 separate body makes body 104
ref_plane "WorkPlane105" through (0, 0, 11) normal (0, 0, 1) x (1, 0, 0)
sketch "tile_N_4_3_0" plane through (0, 0, 11) normal (0, 0, 1) x (1, 0, 0)
  line L0 (80, 10) -> (100, 10)
  line L1 (100, 10) -> (100, 20)
  line L2 (100, 20) -> (80, 20)
  line L3 (80, 20) -> (80, 10)
extrude "Extrude105" add sketch "tile_N_4_3_0" along normal mid plane 5 separate body makes body 105
ref_plane "WorkPlane106" through (0, 0, -11) normal (0, 0, 1) x (1, 0, 0)
sketch "tile_S_4_3_0" plane through (0, 0, -11) normal (0, 0, 1) x (1, 0, 0)
  line L0 (80, 10) -> (100, 10)
  line L1 (100, 10) -> (100, 20)
  line L2 (100, 20) -> (80, 20)
  line L3 (80, 20) -> (80, 10)
extrude "Extrude106" add sketch "tile_S_4_3_0" along normal mid plane 5 separate body makes body 106
ref_plane "WorkPlane107" through (0, 0, 16) normal (0, 0, 1) x (1, 0, 0)
sketch "tile_N_4_3_1" plane through (0, 0, 16) normal (0, 0, 1) x (1, 0, 0)
  line L0 (80, 10) -> (100, 10)
  line L1 (100, 10) -> (100, 20)
  line L2 (100, 20) -> (80, 20)
  line L3 (80, 20) -> (80, 10)
extrude "Extrude107" add sketch "tile_N_4_3_1" along normal mid plane 5 separate body makes body 107
ref_plane "WorkPlane108" through (0, 0, -16) normal (0, 0, 1) x (1, 0, 0)
sketch "tile_S_4_3_1" plane through (0, 0, -16) normal (0, 0, 1) x (1, 0, 0)
  line L0 (80, 10) -> (100, 10)
  line L1 (100, 10) -> (100, 20)
  line L2 (100, 20) -> (80, 20)
  line L3 (80, 20) -> (80, 10)
extrude "Extrude108" add sketch "tile_S_4_3_1" along normal mid plane 5 separate body makes body 108
ref_plane "WorkPlane109" through (0, 0, 11) normal (0, 0, 1) x (1, 0, 0)
sketch "tile_N_5_0_0" plane through (0, 0, 11) normal (0, 0, 1) x (1, 0, 0)
  line L0 (100, -20) -> (120, -20)
  line L1 (120, -20) -> (120, -10)
  line L2 (120, -10) -> (100, -10)
  line L3 (100, -10) -> (100, -20)
extrude "Extrude109" add sketch "tile_N_5_0_0" along normal mid plane 5 separate body makes body 109
ref_plane "WorkPlane110" through (0, 0, -11) normal (0, 0, 1) x (1, 0, 0)
sketch "tile_S_5_0_0" plane through (0, 0, -11) normal (0, 0, 1) x (1, 0, 0)
  line L0 (100, -20) -> (120, -20)
  line L1 (120, -20) -> (120, -10)
  line L2 (120, -10) -> (100, -10)
  line L3 (100, -10) -> (100, -20)
extrude "Extrude110" add sketch "tile_S_5_0_0" along normal mid plane 5 separate body makes body 110
ref_plane "WorkPlane111" through (0, 0, 16) normal (0, 0, 1) x (1, 0, 0)
sketch "tile_N_5_0_1" plane through (0, 0, 16) normal (0, 0, 1) x (1, 0, 0)
  line L0 (100, -20) -> (120, -20)
  line L1 (120, -20) -> (120, -10)
  line L2 (120, -10) -> (100, -10)
  line L3 (100, -10) -> (100, -20)
extrude "Extrude111" add sketch "tile_N_5_0_1" along normal mid plane 5 separate body makes body 111
ref_plane "WorkPlane112" through (0, 0, -16) normal (0, 0, 1) x (1, 0, 0)
sketch "tile_S_5_0_1" plane through (0, 0, -16) normal (0, 0, 1) x (1, 0, 0)
  line L0 (100, -20) -> (120, -20)
  line L1 (120, -20) -> (120, -10)
  line L2 (120, -10) -> (100, -10)
  line L3 (100, -10) -> (100, -20)
extrude "Extrude112" add sketch "tile_S_5_0_1" along normal mid plane 5 separate body makes body 112
ref_plane "WorkPlane113" through (0, 0, 11) normal (0, 0, 1) x (1, 0, 0)
sketch "tile_N_5_1_0" plane through (0, 0, 11) normal (0, 0, 1) x (1, 0, 0)
  line L0 (100, -10) -> (120, -10)
  line L1 (120, -10) -> (120, 0)
  line L2 (120, 0) -> (100, 0)
  line L3 (100, 0) -> (100, -10)
extrude "Extrude113" add sketch "tile_N_5_1_0" along normal mid plane 5 separate body makes body 113
ref_plane "WorkPlane114" through (0, 0, -11) normal (0, 0, 1) x (1, 0, 0)
sketch "tile_S_5_1_0" plane through (0, 0, -11) normal (0, 0, 1) x (1, 0, 0)
  line L0 (100, -10) -> (120, -10)
  line L1 (120, -10) -> (120, 0)
  line L2 (120, 0) -> (100, 0)
  line L3 (100, 0) -> (100, -10)
extrude "Extrude114" add sketch "tile_S_5_1_0" along normal mid plane 5 separate body makes body 114
ref_plane "WorkPlane115" through (0, 0, 16) normal (0, 0, 1) x (1, 0, 0)
sketch "tile_N_5_1_1" plane through (0, 0, 16) normal (0, 0, 1) x (1, 0, 0)
  line L0 (100, -10) -> (120, -10)
  line L1 (120, -10) -> (120, 0)
  line L2 (120, 0) -> (100, 0)
  line L3 (100, 0) -> (100, -10)
extrude "Extrude115" add sketch "tile_N_5_1_1" along normal mid plane 5 separate body makes body 115
ref_plane "WorkPlane116" through (0, 0, -16) normal (0, 0, 1) x (1, 0, 0)
sketch "tile_S_5_1_1" plane through (0, 0, -16) normal (0, 0, 1) x (1, 0, 0)
  line L0 (100, -10) -> (120, -10)
  line L1 (120, -10) -> (120, 0)
  line L2 (120, 0) -> (100, 0)
  line L3 (100, 0) -> (100, -10)
extrude "Extrude116" add sketch "tile_S_5_1_1" along normal mid plane 5 separate body makes body 116
ref_plane "WorkPlane117" through (0, 0, 11) normal (0, 0, 1) x (1, 0, 0)
sketch "tile_N_5_2_0" plane through (0, 0, 11) normal (0, 0, 1) x (1, 0, 0)
  line L0 (100, 0) -> (120, 0)
  line L1 (120, 0) -> (120, 10)
  line L2 (120, 10) -> (100, 10)
  line L3 (100, 10) -> (100, 0)
extrude "Extrude117" add sketch "tile_N_5_2_0" along normal mid plane 5 separate body makes body 117
ref_plane "WorkPlane118" through (0, 0, -11) normal (0, 0, 1) x (1, 0, 0)
sketch "tile_S_5_2_0" plane through (0, 0, -11) normal (0, 0, 1) x (1, 0, 0)
  line L0 (100, 0) -> (120, 0)
  line L1 (120, 0) -> (120, 10)
  line L2 (120, 10) -> (100, 10)
  line L3 (100, 10) -> (100, 0)
extrude "Extrude118" add sketch "tile_S_5_2_0" along normal mid plane 5 separate body makes body 118
ref_plane "WorkPlane119" through (0, 0, 16) normal (0, 0, 1) x (1, 0, 0)
sketch "tile_N_5_2_1" plane through (0, 0, 16) normal (0, 0, 1) x (1, 0, 0)
  line L0 (100, 0) -> (120, 0)
  line L1 (120, 0) -> (120, 10)
  line L2 (120, 10) -> (100, 10)
  line L3 (100, 10) -> (100, 0)
extrude "Extrude119" add sketch "tile_N_5_2_1" along normal mid plane 5 separate body makes body 119
ref_plane "WorkPlane120" through (0, 0, -16) normal (0, 0, 1) x (1, 0, 0)
sketch "tile_S_5_2_1" plane through (0, 0, -16) normal (0, 0, 1) x (1, 0, 0)
  line L0 (100, 0) -> (120, 0)
  line L1 (120, 0) -> (120, 10)
  line L2 (120, 10) -> (100, 10)
  line L3 (100, 10) -> (100, 0)
extrude "Extrude120" add sketch "tile_S_5_2_1" along normal mid plane 5 separate body makes body 120
ref_plane "WorkPlane121" through (0, 0, 11) normal (0, 0, 1) x (1, 0, 0)
sketch "tile_N_5_3_0" plane through (0, 0, 11) normal (0, 0, 1) x (1, 0, 0)
  line L0 (100, 10) -> (120, 10)
  line L1 (120, 10) -> (120, 20)
  line L2 (120, 20) -> (100, 20)
  line L3 (100, 20) -> (100, 10)
extrude "Extrude121" add sketch "tile_N_5_3_0" along normal mid plane 5 separate body makes body 121
ref_plane "WorkPlane122" through (0, 0, -11) normal (0, 0, 1) x (1, 0, 0)
sketch "tile_S_5_3_0" plane through (0, 0, -11) normal (0, 0, 1) x (1, 0, 0)
  line L0 (100, 10) -> (120, 10)
  line L1 (120, 10) -> (120, 20)
  line L2 (120, 20) -> (100, 20)
  line L3 (100, 20) -> (100, 10)
extrude "Extrude122" add sketch "tile_S_5_3_0" along normal mid plane 5 separate body makes body 122
ref_plane "WorkPlane123" through (0, 0, 16) normal (0, 0, 1) x (1, 0, 0)
sketch "tile_N_5_3_1" plane through (0, 0, 16) normal (0, 0, 1) x (1, 0, 0)
  line L0 (100, 10) -> (120, 10)
  line L1 (120, 10) -> (120, 20)
  line L2 (120, 20) -> (100, 20)
  line L3 (100, 20) -> (100, 10)
extrude "Extrude123" add sketch "tile_N_5_3_1" along normal mid plane 5 separate body makes body 123
ref_plane "WorkPlane124" through (0, 0, -16) normal (0, 0, 1) x (1, 0, 0)
sketch "tile_S_5_3_1" plane through (0, 0, -16) normal (0, 0, 1) x (1, 0, 0)
  line L0 (100, 10) -> (120, 10)
  line L1 (120, 10) -> (120, 20)
  line L2 (120, 20) -> (100, 20)
  line L3 (100, 20) -> (100, 10)
extrude "Extrude124" add sketch "tile_S_5_3_1" along normal mid plane 5 separate body makes body 124
named bodies: "low_floor_roof", "low_seat_R", "low_seat_L", "low_out_R", "low_out_L", "low_wall_R", "low_wall_L", "low_end_front", "low_end_back_R", "low_end_back_L", "low_lip_R", "low_lip_L", "up_floor_roof", "up_seat_R", "up_seat_L", "up_out_R", "up_out_L", "up_wall_R", "up_wall_L", "up_end_front", "up_end_back_R", "up_end_back_L", "up_lip_R", "up_lip_L", "graphite_R", "graphite_L", "iron_R", "iron_L", "tile_N_0_0_0", "tile_S_0_0_0", "tile_N_0_0_1", "tile_S_0_0_1", "tile_N_0_1_0", "tile_S_0_1_0", "tile_N_0_1_1", "tile_S_0_1_1", "tile_N_0_2_0", "tile_S_0_2_0", "tile_N_0_2_1", "tile_S_0_2_1", "tile_N_0_3_0", "tile_S_0_3_0", "tile_N_0_3_1", "tile_S_0_3_1", "tile_N_1_0_0", "tile_S_1_0_0", "tile_N_1_0_1", "tile_S_1_0_1", "tile_N_1_1_0", "tile_S_1_1_0", "tile_N_1_1_1", "tile_S_1_1_1", "tile_N_1_2_0", "tile_S_1_2_0", "tile_N_1_2_1", "tile_S_1_2_1", "tile_N_1_3_0", "tile_S_1_3_0", "tile_N_1_3_1", "tile_S_1_3_1", "tile_N_2_0_0", "tile_S_2_0_0", "tile_N_2_0_1", "tile_S_2_0_1", "tile_N_2_1_0", "tile_S_2_1_0", "tile_N_2_1_1", "tile_S_2_1_1", "tile_N_2_2_0", "tile_S_2_2_0", "tile_N_2_2_1", "tile_S_2_2_1", "tile_N_2_3_0", "tile_S_2_3_0", "tile_N_2_3_1", "tile_S_2_3_1", "tile_N_3_0_0", "tile_S_3_0_0", "tile_N_3_0_1", "tile_S_3_0_1", "tile_N_3_1_0", "tile_S_3_1_0", "tile_N_3_1_1", "tile_S_3_1_1", "tile_N_3_2_0", "tile_S_3_2_0", "tile_N_3_2_1", "tile_S_3_2_1", "tile_N_3_3_0", "tile_S_3_3_0", "tile_N_3_3_1", "tile_S_3_3_1", "tile_N_4_0_0", "tile_S_4_0_0", "tile_N_4_0_1", "tile_S_4_0_1", "tile_N_4_1_0", "tile_S_4_1_0", "tile_N_4_1_1", "tile_S_4_1_1", "tile_N_4_2_0", "tile_S_4_2_0", "tile_N_4_2_1", "tile_S_4_2_1", "tile_N_4_3_0", "tile_S_4_3_0", "tile_N_4_3_1", "tile_S_4_3_1", "tile_N_5_0_0", "tile_S_5_0_0", "tile_N_5_0_1", "tile_S_5_0_1", "tile_N_5_1_0", "tile_S_5_1_0", "tile_N_5_1_1", "tile_S_5_1_1", "tile_N_5_2_0", "tile_S_5_2_0", "tile_N_5_2_1", "tile_S_5_2_1", "tile_N_5_3_0", "tile_S_5_3_0", "tile_N_5_3_1", "tile_S_5_3_1"
